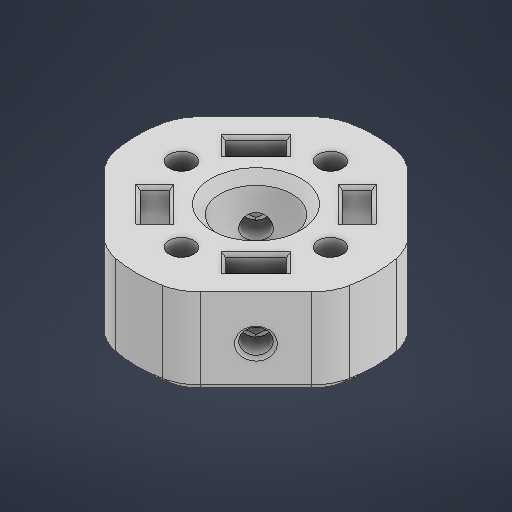
# Autodesk Inventor part: motor_flange
Saved by Autodesk Inventor 2027.1 (Build 311270010, 270A)
## iProperties
Created: 2026-10-09
Part Number: motor_flange
Material: Generic
Document SubType Name: Modeling
Designer: lucao
Density: 0.5302 g/cm^3
Appearance: Default
Mass: 6.98 g
Surface Area: 61.1388 cm^2
Volume: 13.1648 cm^3
Author: lucao
## iProperties of the stored document motor_flange_3DPrint.ipt
Created: 2026-10-13
Part Number: motor_flange_3DPrint
Material: Generic
Document SubType Name: Modeling
Designer: lucao
Density: 1 g/cm^3
Appearance: Default
Author: lucao
Autodesk Inventor part; units mm, degrees
ref_plane "XZ Plane" through (0, 0, 0) normal (0, 1, 0) x (-1, 0, 0)
sketch "Sketch1" plane through (0, 0, 0) normal (0, 1, 0) x (-1, 0, 0)
  circle A0 centre (0, 0) radius 20
  dimension "d0" = 40
  constraints: 1 centre point, 1 coincident
  measures "d0" diameter of A0
extrude "Extrusion1" add sketch "Sketch1" along normal blind 15
sketch "Sketch2" plane through (0, 15, 0) normal (0, 1, 0) x (1, 0, 0)
  circle A0 centre (0, 0) radius 12.5 construction
  circle A1 centre (-12.5, 0) radius 2.05
  circle A2 centre (0, 12.5) radius 2.05
  circle A3 centre (12.5, 0) radius 2.05
  circle A4 centre (0, -12.5) radius 2.05
  dimension "d3" = 25
  dimension "d4" = 4.1
  dimension "d5" = 4.1
  dimension "d6" = 4.1
  dimension "d7" = 4.1
  constraints: 5 centre point, 4 point on circle, 2 horizontal alignment, 2 vertical alignment, 1 coincident
  measures "d3" diameter of A0
  measures "d4" diameter of A1
  measures "d5" diameter of A2
  measures "d6" diameter of A3
  measures "d7" diameter of A4
extrude "Extrusion2" cut sketch "Sketch2" against normal through all
sketch "Sketch3" plane through (0, 15, 0) normal (0, 1, 0) x (1, 0, 0)
  circle A0 centre (0, 0) radius 6.025
  dimension "d10" = 12.05
  constraints: 1 centre point, 1 coincident
  measures "d10" diameter of A0
extrude "Extrusion3" cut sketch "Sketch3" against normal through all
sketch "Sketch4" plane through (0, 15, 0) normal (0, 1, 0) x (1, 0, 0)
  circle A0 centre (0, 0) radius 6.025 projected
  circle A1 centre (12.5, 0) radius 2.05 projected
  circle A2 centre (0, -12.5) radius 2.05 projected
  circle A3 centre (0, 12.5) radius 2.05 projected
  circle A4 centre (-12.5, 0) radius 2.05 projected
  circle A5 centre (0, 0) radius 20 projected
  line L0 (-6.5635, -18.8923) -> (-18.8923, -6.5635)
  circle A6 centre (0, 0) radius 20 projected
  line L1 (0, 0) -> (-12.7279, -12.7279) construction
  line L2 (0, 0) -> (0, -12.6366) construction
  dimension "d19" = 45
  dimension "d20" = 18
  constraints: 6 end point, 1 midpoint, 1 perpendicular, 1 point on circle, 1 vertical, 2 other
  measures "d19" angle of L2 L1
  measures "d20" distance from line of point (0, 0) L0
extrude "Extrusion4" cut sketch "Sketch4" against normal through all contours L0 A5 picked at (-14.134, -12.0259)
sketch "Sketch5" plane through (-6.5635, 0, 18.8923) normal (-0.7071068, 0, 0.7071068) x (0.7071068, 0, 0.7071068)
  line L0 (-2.6928, 0) -> (-14.7428, 0) projected
  line L1 (-14.7428, 15) -> (-2.6928, 15) projected
  circle A0 centre (-8.7178, 7.5) radius 2.05
  line L2 (-17.4356, 0) -> (-17.4356, 15) projected
  point P0 (-8.7178, 0)
  point P1 (-17.4356, 7.5)
  point P2 (-8.7178, 15)
  dimension "d23" = 4.1
  constraints: 2 midpoint, 1 centre point, 1 horizontal alignment, 1 vertical alignment
  measures "d23" diameter of A0
ref_plane "Work Plane1" through (0, 0, 0) normal (0.7071068, 0, -0.7071068) x (0, 1, 0)
extrude "Extrusion5" cut sketch "Sketch5" against normal up to surface (18 mm away)
ref_plane "Work Plane2" through (-2.3209, 0, 14.6497) normal (-0.7071068, 0, 0.7071068) x (0.7071068, 0, 0.7071068)
sketch "Sketch7" plane through (-2.3209, 0, 14.6497) normal (-0.7071068, 0, 0.7071068) x (0.7071068, 0, 0.7071068)
  spline S0 degree 2 poles (-6.6678, 7.5) (-6.6678, 11.0507) (-9.7428, 9.2754) (-12.8178, 7.5) (-9.7428, 5.7246) (-6.6678, 3.9493) (-6.6678, 7.5) knots 0 0 0 0.333333 0.333333 0.666667 0.666667 1 1 1 weights 1 0.5 1 0.5 1 0.5 1 projected
  line L0 (-5.1178, 9.5785) -> (-5.1178, 5.4215)
  line L1 (-5.1178, 5.4215) -> (-8.7178, 3.3431)
  line L2 (-8.7178, 3.3431) -> (-12.3178, 5.4215)
  line L3 (-12.3178, 5.4215) -> (-12.3178, 9.5785)
  line L4 (-12.3178, 9.5785) -> (-8.7178, 11.6569)
  line L5 (-8.7178, 11.6569) -> (-5.1178, 9.5785)
  line L6 (0, 15) -> (0, 0) projected
  line L7 (0, 0) -> (-17.4356, 0) projected
  line L8 (-17.4356, 0) -> (-17.4356, 15) projected
  line L9 (0, 15) -> (-17.4356, 15) projected
  line L10 (-12.3178, 9.5785) -> (-12.3178, 15)
  line L11 (-5.1178, 9.5785) -> (-5.1178, 15)
  point P0 (-8.7178, 0)
  point P1 (-8.7178, 7.5)
  point P2 (0, 7.5)
  point P3 (-8.7178, 15)
  dimension "d27" = 7.2
  constraints: 16 end point, 2 midpoint, 2 perpendicular, 2 point on line, 1 horizontal alignment, 1 parallel, 1 vertical alignment, 14 other
  measures "d27" distance between parallel lines of L3 L0
extrude "Extrusion6" cut sketch "Sketch7" along normal mid plane 3.5 contours L0 L1 L2 L3 L4 L5 | L5 L4 L10 L9 L11
chamfer "Chamfer3" distance 0.5 angle 45 4 edges at (-7.2464, 15, 7.2464) (-11.0309, 15, 5.9397) (-9.7241, 15, 9.7241) (-5.9397, 15, 11.0309)
chamfer "Chamfer4" distance 0.5 angle 45 1 edges at (-14.1775, 7.5, 11.2784)
pattern_circular "Circular Pattern1" count 4 over 360 about axis through (0, 15, 0) along (0, -1, 0) of "Extrusion4", "Extrusion5", "Extrusion6", "Chamfer3", "Chamfer4"
fillet "Fillet1" radius 8 8 edges at (-6.5635, 7.5, -18.8923) (6.5635, 7.5, -18.8923) (18.8923, 7.5, -6.5635) (18.8923, 7.5, 6.5635) (6.5635, 7.5, 18.8923) (-6.5635, 7.5, 18.8923) (-18.8923, 7.5, 6.5635) (-18.8923, 7.5, -6.5635)
chamfer "Chamfer5" distance 1.5 angle 45 1 edges at (-6.025, 15, 0)
chamfer "Chamfer6" distance 1.5 angle 45 16 edges at (-12.7279, 0, 12.7279) (-18.8105, 0, 6.1637) (-20, 0, 0) (-18.8105, 0, -6.1637) (-12.7279, 0, -12.7279) (-6.1637, 0, -18.8105) (0, 0, -20) (6.1637, 0, -18.8105) (12.7279, 0, -12.7279) (18.8105, 0, -6.1637) (20, 0, 0) (18.8105, 0, 6.1637) (12.7279, 0, 12.7279) (6.1637, 0, 18.8105) (0, 0, 20) (-6.1637, 0, 18.8105)
ref_plane "Work Plane3" through (0, 0, 0) normal (0.7071068, 0, 0.7071068) x (0, 1, 0)
ref_plane "Work Plane4" through (0, 0, 0) normal (-0.7071068, 0, 0.7071068) x (0, 1, 0)
ref_plane "Work Plane5" through (0, 0, 0) normal (-0.7071068, 0, -0.7071068) x (0, 1, 0)
ref_plane "Work Plane6" through (-14.6497, 0, -2.3209) normal (-0.7071068, 0, -0.7071068) x (-0.7071068, 0, 0.7071068)
ref_plane "Work Plane7" through (2.3209, 0, -14.6497) normal (0.7071068, 0, -0.7071068) x (-0.7071068, 0, -0.7071068)
ref_plane "Work Plane8" through (14.6497, 0, 2.3209) normal (0.7071068, 0, 0.7071068) x (0.7071068, 0, -0.7071068)
body "Solid1"
